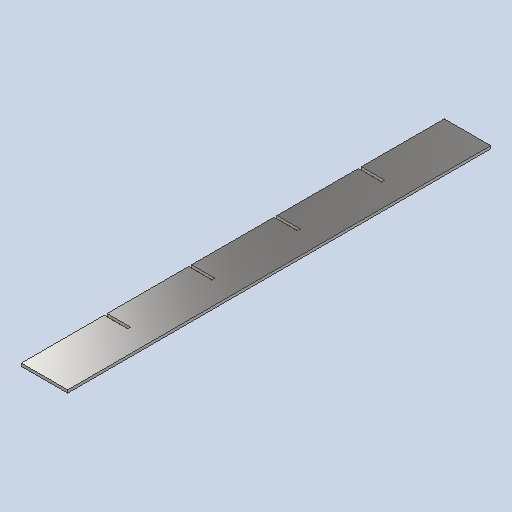
# Autodesk Inventor part: RDS-1206 Grate Strip Long
Saved by Autodesk Inventor 2026.2 (Build 302298000, 298)
## iProperties
Created: 2026-10-18
Part Number: RDS-1206 Grate Strip Long
Material: Stainless Steel, Austenitic
Description: Grate strip long, on edge, slots from bottom, AISI 304 3 mm
Document SubType Name: Sheet Metal
Designer: admin
Stock Number: Колосник продольный 3 мм (×3)
Density: 8 g/cm^3
Flat Pattern Width: 5 cm
Flat Pattern Length: 45.6 cm
Flat Pattern Area: 228 cm^2
Sheet Metal Rule: Default
Sheet Metal Width: 50,000 mm
Sheet Metal Length: 456,000 mm
Sheet Metal Area: 22800,000 mm^2
Appearance: Semi-Polished
Author: admin
Autodesk Inventor part; units mm, degrees
ref_plane "YZ Plane" through (0, 0, 0) normal (1, 0, 0) x (0, 1, 0)
ref_plane "XZ Plane" through (0, 0, 0) normal (0, 1, 0) x (-1, 0, 0)
ref_plane "XY Plane" through (0, 0, 0) normal (0, 0, 1) x (1, 0, 0)
sketch "Sketch1" plane through (0, 0, 0) normal (0, 1, 0) x (-1, 0, 0)
  line L0 (25, -228) -> (-25, -228)
  line L1 (-25, -228) -> (-25, 228)
  line L2 (-25, 228) -> (25, 228)
  line L3 (25, 228) -> (25, -228)
  dimension "d0" = 50
  dimension "d1" = 456
  measures "d0" distance of L0.start L0.end
  measures "d1" distance of L0.end L1.end
extrude "Plate1" add sketch "Sketch1" along normal blind 3
sketch "Sketch2" plane through (0, 3, 0) normal (0, 1, 0) x (1, 0, 0)
  line L0 (-25, 138.6) -> (0, 138.6)
  line L1 (0, 138.6) -> (0, 135.4)
  line L2 (0, 135.4) -> (-25, 135.4)
  line L3 (-25, 135.4) -> (-25, 138.6)
  line L4 (-25, 47.6) -> (0, 47.6)
  line L5 (0, 47.6) -> (0, 44.4)
  line L6 (0, 44.4) -> (-25, 44.4)
  line L7 (-25, 44.4) -> (-25, 47.6)
  line L8 (-25, -44.4) -> (0, -44.4)
  line L9 (0, -44.4) -> (0, -47.6)
  line L10 (0, -47.6) -> (-25, -47.6)
  line L11 (-25, -47.6) -> (-25, -44.4)
  line L12 (-25, -135.4) -> (0, -135.4)
  line L13 (0, -135.4) -> (0, -138.6)
  line L14 (0, -138.6) -> (-25, -138.6)
  line L15 (-25, -138.6) -> (-25, -135.4)
  constraints: 32 end point, 8 parallel, 4 horizontal, 4 perpendicular
extrude "Cut1" cut sketch "Sketch2" against normal blind 3
equation "\"d0\" = Grate1206_Width"
equation "\"d1\" = Grate1206_Length"
equation "\"d2\" = Thickness"
equation "\"BendRadius\" = Thickness"
equation "\"BendReliefWidth\" = Thickness"
equation "\"BendReliefDepth\" = 0.5 * Thickness"
equation "\"CornerReliefSize\" = 4 * Thickness"
equation "\"MinimumRemnant\" = 2 * Thickness"
equation "\"TransitionRadius\" = BendRadius"
equation "\"JacobiRadiusSize\" = BendRadius"
equation "\"GapSize\" = Thickness"
equation "\"Grate1206_Width\" = 50"
equation "\"Grate1206_Length\" = 456"
equation "\"Thickness\" = 3"
body "Solid1"
